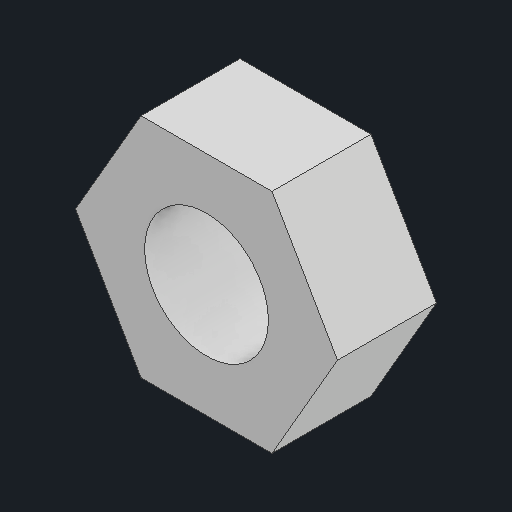
# Autodesk Inventor part: Tuerca_M3_referencia
Saved by Autodesk Inventor 2027.2 (Build 312334000, 334)
## iProperties
Created: 2026-11-15
Part Number: Tuerca_M3_referencia
Material: Genérico
Document SubType Name: Modeling
Designer: alexa
Density: 1 g/cm^3
Appearance: Valor por defecto
Mass: 0.0459088 g
Surface Area: 1.06603 cm^2
Volume: 0.0459088 cm^3
Author: alexa
Autodesk Inventor part; units mm, degrees
ref_plane "YZ Plane" through (0, 0, 0) normal (1, 0, 0) x (0, 1, 0)
ref_plane "XZ Plane" through (0, 0, 0) normal (0, 1, 0) x (-1, 0, 0)
sketch "Tuerca_hexagonal_perfil" plane through (0, 0, 0) normal (0, 0, 1) x (1, 0, 0)
  line L0 (3.1754, 0) -> (1.5877, 2.75)
  line L1 (1.5877, 2.75) -> (-1.5877, 2.75)
  line L2 (-1.5877, 2.75) -> (-3.1754, 0)
  line L3 (-3.1754, 0) -> (-1.5877, -2.75)
  line L4 (-1.5877, -2.75) -> (1.5877, -2.75)
  line L5 (1.5877, -2.75) -> (3.1754, 0)
  constraints: 12 end point
extrude "Tuerca_hexagonal" add sketch "Tuerca_hexagonal_perfil" along normal blind 2.4
ref_plane "Plano de trabajo1" through (0, 0, -0.1) normal (0, 0, 1) x (1, 0, 0)
sketch "Paso_rosca_nominal_perfil" plane through (0, 0, -0.1) normal (0, 0, 1) x (1, 0, 0)
  circle A0 centre (0, 0) radius 1.5
  constraints: 1 centre point
extrude "Paso_rosca_nominal" cut sketch "Paso_rosca_nominal_perfil" along normal blind 2.6
